MOD-GRID Olight iMini 2 Holder (Autodesk Fusion 360 design; units mm, degrees)
part number: 2026-10-26-19-07-41-889
Autodesk Fusion 360 part; units mm, degrees
ref_plane "WorkPlane38" through (1, 0, 0) normal (1, 0, 0) x (0, 1, 0)
sketch "Cap section" plane through (1, 0, 0) normal (1, 0, 0) x (0, 0, -1)
  circle A0 centre (-13.55, 0) radius 7.55
extrude "Extrude60" add sketch "Cap section" along normal blind 15 makes body 1
ref_plane "WorkPlane39" through (16, 0, 0) normal (1, 0, 0) x (0, 1, 0)
sketch "Body section" plane through (16, 0, 0) normal (1, 0, 0) x (0, 0, -1)
  circle A0 centre (-13.55, 0) radius 6.625
extrude "Extrude61" add sketch "Body section" along normal blind 40 bodies 1
ref_plane "WorkPlane40" through (6, 0, 0) normal (1, 0, 0) x (0, 1, 0)
sketch "Band A body" plane through (6, 0, 0) normal (1, 0, 0) x (0, 0, -1)
  line L0 (0, -14.35) -> (-18.3446, -14.35)
  line L1 (-18.3446, -14.35) -> (-18.3446, 14.35)
  line L2 (-18.3446, 14.35) -> (0, 14.35)
  line L3 (0, 14.35) -> (0, -14.35)
extrude "Extrude62" add sketch "Band A body" along normal blind 6 and the other way blind 6 separate body makes body 2
fillet "Fillet15" radius 1.5 4 edges at (6, 14.35, 0) (6, -14.35, 0) (6, -14.35, 18.3446) (6, 14.35, 18.3446) on bodies 2
sketch "Band A cradle" plane through (6, 0, 0) normal (1, 0, 0) x (0, 0, -1)
  arc A0 (-6, 0) -> (-13.75, 7.75) centre (-13.75, 0) ccw
  arc A1 (-16.9118, 7.3172) -> (-16.3461, 7.3172) centre (-16.629, 7.6) ccw
  line L0 (-13.75, 7.75) -> (-15.9133, 7.75)
  line L1 (-15.9133, 7.75) -> (-16.3461, 7.3172)
  line L2 (-16.9118, 7.3172) -> (-17.3446, 7.75)
  line L3 (-17.3446, 7.75) -> (-20.3446, 7.75)
  arc A2 (-13.75, -7.75) -> (-6, 0) centre (-13.75, 0) ccw
  arc A3 (-16.3461, -7.3172) -> (-16.9118, -7.3172) centre (-16.629, -7.6) ccw
  line L4 (-13.75, -7.75) -> (-15.9133, -7.75)
  line L5 (-15.9133, -7.75) -> (-16.3461, -7.3172)
  line L6 (-16.9118, -7.3172) -> (-17.3446, -7.75)
  line L7 (-17.3446, -7.75) -> (-20.3446, -7.75)
  line L8 (-20.3446, -7.75) -> (-20.3446, 7.75)
extrude "Extrude63" cut sketch "Band A cradle" along normal blind 12 and the other way blind 12 bodies 2
sketch "Band A relief" plane through (6, 0, 0) normal (1, 0, 0) x (0, 0, -1)
  arc A0 (-3.7542, 1.7625) -> (-13.75, 10.15) centre (-13.75, 0) ccw
  arc A1 (-2.5724, 1.9709) -> (-13.75, 11.35) centre (-13.75, 0) ccw
  line L0 (-13.75, 10.15) -> (-17.75, 9.35)
  line L1 (-17.75, 9.35) -> (-20.3446, 9.35)
  line L2 (-20.3446, 9.35) -> (-20.3446, 11.35)
  line L3 (-20.3446, 11.35) -> (-13.75, 11.35)
  line L4 (-2.5724, 1.9709) -> (-3.7542, 1.7625)
  circle A2 centre (-3.1633, 1.8667) radius 0.6
  arc A3 (-13.75, -10.15) -> (-3.7542, -1.7625) centre (-13.75, 0) ccw
  arc A4 (-13.75, -11.35) -> (-2.5724, -1.9709) centre (-13.75, 0) ccw
  line L5 (-13.75, -10.15) -> (-17.75, -9.35)
  line L6 (-17.75, -9.35) -> (-20.3446, -9.35)
  line L7 (-20.3446, -9.35) -> (-20.3446, -11.35)
  line L8 (-20.3446, -11.35) -> (-13.75, -11.35)
  line L9 (-2.5724, -1.9709) -> (-3.7542, -1.7625)
  circle A5 centre (-3.1633, -1.8667) radius 0.6
extrude "Extrude64" cut sketch "Band A relief" along normal blind 12 and the other way blind 12 bodies 2
chamfer "Chamfer15" distance 0.5 angle 45 14 edges at (0, 12.1, 18.3446) (0, 13.9107, 17.9053) (0, 14.35, 9.1723) (0, 13.9107, 0.4393) (0, 0, 0) (0, -13.9107, 0.4393) (0, -14.35, 9.1723) (0, -13.9107, 17.9053) (0, -12.1, 18.3446) (0, -8.55, 18.3446) (0, -7.75, 14.8316) (0, 0, 6) (0, 7.75, 14.8316) (0, 8.55, 18.3446) tangent chain off on bodies 2
ref_plane "WorkPlane41" through (0, 0, 0) normal (1, 0, 0) x (0, 1, 0)
sketch "Band A legs" plane through (0, 0, 0) normal (1, 0, 0) x (0, 0, -1)
  line L0 (-0.5, -9.45) -> (4.64, -9.45)
  line L1 (4.64, -9.45) -> (4.64, -9.93)
  line L2 (4.64, -9.93) -> (3.4, -11.19)
  line L3 (3.4, -11.19) -> (3.1, -10.32)
  line L4 (3.1, -10.32) -> (-0.5, -10.32)
  line L5 (-0.5, -10.32) -> (-0.5, -9.45)
  line L6 (-0.5, -6.55) -> (4.64, -6.55)
  line L7 (4.64, -6.55) -> (4.64, -6.07)
  line L8 (4.64, -6.07) -> (3.4, -4.81)
  line L9 (3.4, -4.81) -> (3.1, -5.68)
  line L10 (3.1, -5.68) -> (-0.5, -5.68)
  line L11 (-0.5, -5.68) -> (-0.5, -6.55)
  line L12 (-0.5, 6.55) -> (4.64, 6.55)
  line L13 (4.64, 6.55) -> (4.64, 6.07)
  line L14 (4.64, 6.07) -> (3.4, 4.81)
  line L15 (3.4, 4.81) -> (3.1, 5.68)
  line L16 (3.1, 5.68) -> (-0.5, 5.68)
  line L17 (-0.5, 5.68) -> (-0.5, 6.55)
  line L18 (-0.5, 9.45) -> (4.64, 9.45)
  line L19 (4.64, 9.45) -> (4.64, 9.93)
  line L20 (4.64, 9.93) -> (3.4, 11.19)
  line L21 (3.4, 11.19) -> (3.1, 10.32)
  line L22 (3.1, 10.32) -> (-0.5, 10.32)
  line L23 (-0.5, 10.32) -> (-0.5, 9.45)
extrude "Extrude65" add sketch "Band A legs" along normal blind 4.76 bodies 2
ref_plane "WorkPlane42" through (28, 0, 0) normal (1, 0, 0) x (0, 1, 0)
sketch "Band B body" plane through (28, 0, 0) normal (1, 0, 0) x (0, 0, -1)
  line L0 (0, -14.35) -> (-12.75, -14.35)
  line L1 (-12.75, -14.35) -> (-12.75, 14.35)
  line L2 (-12.75, 14.35) -> (0, 14.35)
  line L3 (0, 14.35) -> (0, -14.35)
extrude "Extrude66" add sketch "Band B body" along normal blind 12 and the other way blind 12 separate body makes body 3
fillet "Fillet16" radius 1.5 4 edges at (28, 14.35, 0) (28, -14.35, 0) (28, -14.35, 12.75) (28, 14.35, 12.75) on bodies 3
sketch "Band B cradle" plane through (28, 0, 0) normal (1, 0, 0) x (0, 0, -1)
  arc A0 (-6.925, 0) -> (-12.75, 6.7513) centre (-13.75, 0) ccw
  arc A1 (-12.75, -6.7513) -> (-6.925, 0) centre (-13.75, 0) ccw
  line L0 (-12.75, -6.7513) -> (-12.75, 6.7513)
extrude "Extrude67" cut sketch "Band B cradle" along normal blind 24 and the other way blind 24 bodies 3
chamfer "Chamfer16" distance 0.5 angle 45 9 edges at (16, 9.8007, 12.75) (16, 13.9107, 12.3107) (16, 14.35, 6.375) (16, 13.9107, 0.4393) (16, 0, 0) (16, -13.9107, 0.4393) (16, -14.35, 6.375) (16, -13.9107, 12.3107) (16, -9.8007, 12.75) tangent chain off on bodies 3
ref_plane "WorkPlane43" through (16, 0, 0) normal (1, 0, 0) x (0, 1, 0)
sketch "Band B legs" plane through (16, 0, 0) normal (1, 0, 0) x (0, 0, -1)
  line L0 (-0.5, -9.45) -> (4.64, -9.45)
  line L1 (4.64, -9.45) -> (4.64, -9.93)
  line L2 (4.64, -9.93) -> (3.4, -11.19)
  line L3 (3.4, -11.19) -> (3.1, -10.32)
  line L4 (3.1, -10.32) -> (-0.5, -10.32)
  line L5 (-0.5, -10.32) -> (-0.5, -9.45)
  line L6 (-0.5, -6.55) -> (4.64, -6.55)
  line L7 (4.64, -6.55) -> (4.64, -6.07)
  line L8 (4.64, -6.07) -> (3.4, -4.81)
  line L9 (3.4, -4.81) -> (3.1, -5.68)
  line L10 (3.1, -5.68) -> (-0.5, -5.68)
  line L11 (-0.5, -5.68) -> (-0.5, -6.55)
  line L12 (-0.5, 6.55) -> (4.64, 6.55)
  line L13 (4.64, 6.55) -> (4.64, 6.07)
  line L14 (4.64, 6.07) -> (3.4, 4.81)
  line L15 (3.4, 4.81) -> (3.1, 5.68)
  line L16 (3.1, 5.68) -> (-0.5, 5.68)
  line L17 (-0.5, 5.68) -> (-0.5, 6.55)
  line L18 (-0.5, 9.45) -> (4.64, 9.45)
  line L19 (4.64, 9.45) -> (4.64, 9.93)
  line L20 (4.64, 9.93) -> (3.4, 11.19)
  line L21 (3.4, 11.19) -> (3.1, 10.32)
  line L22 (3.1, 10.32) -> (-0.5, 10.32)
  line L23 (-0.5, 10.32) -> (-0.5, 9.45)
extrude "Extrude68" add sketch "Band B legs" along normal blind 4.76 bodies 3
equation "part_d = 13.25 mm" comment "Cylinder diameter. RETAILER SPEC (PB Tech / Adorama both list 55 x 15.1 mm, 19.5 g), NOT caliper-checked - hence the looser lip_clear."
equation "part_len = 55.0 mm" comment "Cylinder length - sets where the reference body ends and how far apart the bands can sit."
equation "base_t = 6.00 mm" comment "Base under the part. It sets how far the slot root sits above the z=0 face; run() checks it."
equation "cav_clear = 0.40 mm" comment "Clearance on the cradle DIAMETER (total). On a ROUND part this is close to free, which is not true of the flat-walled bands: a cylinder nests at the bottom of a larger cylindrical cradle and self-centres there, so extra clearance buys tolerance without buying rattle. It is also provably free at the lip - cav_hw cancels out of lip_zt and out of K, so the splay, the push force, the stress and the seated lip clearance are all identical at any value; only the band gets wider. Set at 1.00 (0.86 as printed) so the cradle tolerates the diameter being 0.86 mm over nominal, which is the number that runs out first."
equation "cav_r = grip_d / 2 + cav_clear / 2" comment "Cradle radius. LARGER than the part on purpose. For a rounded rectangle the rule is the other way round - a cavity corner rounder than the part lands on its corners and holds it off the floor - but a cradle arc larger than a cylinder touches at ONE point at the bottom and cannot jam. Also the arc the relief slot follows."
equation "cav_hw = cav_r" comment "Half width of the straight walls above the cradle. Equal to cav_r, because the walls are tangent to the bore at its equator."
equation "bore_z = base_t + cav_r" comment "Height of the cradle centre"
equation "part_z = base_t + grip_d / 2" comment "Height of the part axis when seated. It sits cav_clear/2 BELOW bore_z, because a smaller cylinder in a larger cradle rests at the bottom."
equation "arm_root = 2.40 mm" comment "Arm thickness AT THE ROOT = 6 extrusions at 0.4. Tapered, because the bending moment is largest at the root and nearly zero at the lip."
equation "arm_tip = 1.60 mm" comment "Arm thickness at the lip = 4 extrusions. Never below 4: 1.2 mm is 2.86 extrusions and the slicer lays a gap-fill bond line down the middle of the flexure."
equation "arm_blend = 4.00 mm" comment "Height above the bore centre over which arm_root blends down to arm_tip."
equation "relief_w = 1.20 mm" comment "Relief slot width behind the arm"
equation "relief_a0 = -80 deg" comment "Relief slot root angle about the BORE CENTRE. The flat-walled bands run -110, but their slot wraps a corner that is offset far to one side. Here it wraps the axis, so at -90 the two slots meet on the centreline and cut the band in two. -80 leaves a column run() measures."
equation "rail_t = 3.00 mm" comment "Outer rail beyond the relief slot"
equation "lip_clear = 0.25 mm" comment "Gap between the lip's underside and the part when seated. For a cylinder this comes out EXACTLY lip_clear whatever the diameter, so what it really buys is tolerance to the diameter being wrong: a part dia_err bigger than nominal eats 0.854 * dia_err of it. Sized from how well the diameter is known."
equation "lip_over = 0.35 mm" comment "How far each lip reaches inboard of the part's widest point - and therefore the splay each arm takes. This IS the deflection, so it sets both the push force and the bending stress. Budgeted against ~25 N of push first and the 15 MPa limit second."
equation "lip_tipr = 0.40 mm" comment "Radius on the lip tip = ONE NOZZLE WIDTH. A knife edge will not print, and a flat land would park the part for its full width; a radius parks it for ~0.23 mm and presents a 45 deg cam immediately below."
equation "lip_tip_y = grip_d / 2 - lip_over" comment "Innermost point of the lip"
equation "lip_apex_y = lip_tip_y - 0.4142135624 * lip_tipr" comment "Virtual apex where the two 45 deg faces would meet if the tip were not rounded"
equation "lip_proj = cav_hw - lip_apex_y" comment "How far the apex stands proud of the wall. At 45 deg this is also the RISE of each face."
equation "lip_z0 = part_z + sqrt(( ( grip_d / 2 + lip_clear + lip_tipr ) / 1 mm ) ^ 2 - ( lip_cy / 1 mm ) ^ 2) * 1 mm - lip_proj" comment "Foot of the capture ramp. Derived: the underside is the line y + z = cav_hw + lip_z0, and this is the lowest it can sit while standing lip_clear off a cylinder of diameter part_d resting in the cradle. The part radius CANCELS out of the clearance, which is why this holder needs no corner-radius estimate."
equation "lip_zt = lip_z0 + lip_proj" comment "Height of the lip tip = where the load is applied to the arm"
equation "land_h = 1.00 mm" comment "Band height above the lip"
equation "band_len = band_a_len" comment "Band width along the part = part height when printed. Grip scales with it and peak stress does not."
equation "band_hw = cav_hw + arm_root + relief_w + rail_t" comment "Band half width"
equation "band_h = lip_z0 + 2 * lip_proj + land_h" comment "Band overall height"
equation "band_a_x = 0 mm" comment "Band A bed face"
equation "band_cells = 2" comment "Grid cells between the two bands. Set so both bands land on the part with a margin at each end."
equation "grid_pitch = 8 mm" comment "MOD-GRID pitch"
equation "band_b_x = band_a_x + band_cells * grid_pitch" comment "Band B bed face"
equation "body_corner_r = 1.50 mm" comment "Rounded outer corners"
equation "first_layer_cham = 0.50 mm" comment "Elephant-foot chamfer on the bed face"
equation "leg_pair_y = 8.0 mm" comment "Leg pairs at +/- this; 16 mm apart = 2 cells. Not 12 like the Zippo: these bands are only ~30 mm wide and the shank would run within 0.1 mm of the outer face."
equation "leg_clear = 0.14 mm" comment "Shrinks the leg LENGTH and SHANK (not the barb). MEASURED: this printer runs 0.07 per wall."
equation "leg_hole_len = 4.90 mm - leg_clear" comment "Leg extent along the print axis"
equation "leg_inner_hw = 1.45 mm" comment "Leg inner face from pair centre -> 2.90 gap"
equation "leg_shank_hw = 2.39 mm - leg_clear / 2" comment "Relaxed shank half-span"
equation "barb_hw = 3.19 mm" comment "Barb peak half-span - NOT reduced, it is meant to squeeze"
equation "barb_z = -3.40 mm" comment "Barb peak depth below the seating face"
equation "catch_z = -3.10 mm" comment "Catch face: 0.10 below the 3.00 plate"
equation "leg_tip_z = -4.64 mm" comment "Leg tip"
equation "leg_tip_hw = 2.00 mm - leg_clear / 2" comment "Tip half-span, sets the ~45 deg lead-in"
equation "grip_d = 15.10 mm" comment "The diameter the SNAP band grips. Normally the same as part_d; it is separate only because a part can be two pieces of different diameter - the Olight's snap band sits on its magnetic CAP while its cradle band sits on the BODY. Every lip number derives from this one, not from part_d."
equation "band_a_len = 12.0 mm" comment "Band A width along the part = its height when printed. Grip scales with it and peak stress does not. On the Olight it is cut to 12 so the whole band lands on the 15-20 mm cap and never straddles the step onto the body."
equation "band_b_len = 24.0 mm" comment "Band B width along the part"
equation "cradle_r = part_d / 2 + cav_clear / 2" comment "Cradle radius of a CRADLE band, off part_d rather than grip_d."
equation "cradle_z = part_z + cradle_r - part_d / 2" comment "Cradle centre, sunk so the part sits on the SAME AXIS as it does in the snap band. Get this wrong and the two bands hold the part at different heights and it rocks."
equation "cradle_drop = 1.00 mm" comment "How far the cradle band's top face stops BELOW its own centre. It must exceed cav_clear/2, or the walls rise past the part's widest point and the part is trapped in a rigid band with no arms to let it out. run() checks it. It also avoids ending the wall on a tangent knife edge."
equation "cradle_h = cradle_z - cradle_drop" comment "Cradle band overall height"
equation "lip_cy = lip_apex_y + 1.4142135624 * lip_tipr" comment "Centre of the lip's tip radius. This is the point the seated part is actually closest to, so it - not the 45 deg face - is what lip_clear has to be measured from."
equation "cap_len = 15.0 mm" comment "Length of the GRIP section (the cap) along the axis, measured from the part's end to the step. Only a stepped part has one; for a plain cylinder it is the whole length. **It does not shape the holder at all** - the bands are where the grid puts them - it only decides how much of Band A lands on the cap, which run() checks and reports. It is the one number on this light still not measured, so it is set to the SHORT end of the 15-20 estimate: too short only under-reports the grip, while too long would over-report it."
equation "d358 = band_b_x - cap_len"
equation "d360 = cap_len"
equation "d362 = band_b_x"
equation "d364 = part_len - cap_len"
equation "d366 = band_a_x + band_a_len / 2"
equation "d368 = band_a_len / 2"
equation "d370 = band_a_len / 2"
equation "d373 = body_corner_r"
equation "d374 = band_a_len"
equation "d376 = band_a_len"
equation "d378 = band_a_len"
equation "d380 = band_a_len"
equation "d382 = first_layer_cham"
equation "d383 = band_a_x"
equation "d385 = leg_hole_len"
equation "d387 = band_b_x + band_b_len / 2"
equation "d389 = band_b_len / 2"
equation "d391 = band_b_len / 2"
equation "d394 = body_corner_r"
equation "d395 = band_b_len"
equation "d397 = band_b_len"
equation "d399 = first_layer_cham"
equation "d400 = band_b_x"
equation "d402 = leg_hole_len"
named bodies: "Reference - Olight i Mini 2", "Band A", "Band B"
